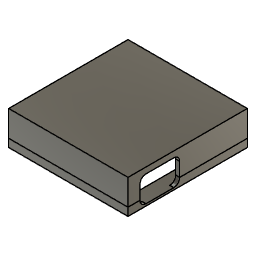
ESP32_Housing (Autodesk Fusion 360 design; units mm, degrees)
Autodesk Fusion 360 part; units mm, degrees
sketch "Sketch1" plane through (0, 0, 0) normal (0, 0, 1) x (1, 0, 0)
  line L0 (0, 0) -> (60, 0)
  line L1 (60, 0) -> (60, 60)
  line L2 (60, 60) -> (0, 60)
  line L3 (0, 60) -> (0, 0)
  line L4 (2, 2) -> (58, 2)
  line L5 (58, 2) -> (58, 58)
  line L6 (58, 58) -> (2, 58)
  line L7 (2, 58) -> (2, 2)
  line L8 (7.5, 7.5) -> (52.5, 7.5)
  line L9 (52.5, 7.5) -> (52.5, 52.5)
  line L10 (52.5, 52.5) -> (7.5, 52.5)
  line L11 (7.5, 52.5) -> (7.5, 7.5)
  dimension "d1" = 60
  dimension "d2" = 60
  dimension "d3" = 56
  dimension "d4" = 56
  dimension "d5" = 2
  dimension "d6" = 2
  dimension "d7" = 45
  dimension "d8" = 45
  dimension "d9" = 7.5
  dimension "d10" = 7.5
  constraint horizontal L0
  constraint vertical L1
  constraint horizontal L2
  constraint vertical L3
  constraint coincident L0.start L3.end
  constraint horizontal L4
  constraint vertical L5
  constraint horizontal L6
  constraint vertical L7
  constraint horizontal L8
  constraint vertical L9
  constraint horizontal L10
  constraint vertical L11
  measures "d1" distance of L0.start L0.end
  measures "d2" distance of L0.start L2.end
  measures "d3" distance of L4.start L4.end
  measures "d4" distance of L4.start L6.end
  measures "d5" distance of L3 L7
  measures "d6" distance of L0 L4
  measures "d7" distance of L8.start L8.end
  measures "d8" distance of L8.start L10.end
  measures "d9" distance of L3 L11
  measures "d10" distance of L0 L8
extrude "Extrude1" add sketch "Sketch1" along normal blind 1 contours L4 L5 L6 L7 makes body 1
extrude "Extrude2" add sketch "Sketch1" along normal blind 4 contours L0 L1 L2 L3 bodies 1
sketch "Sketch2" plane through (0, 0, 4) normal (0, 0, 1) x (-1, 0, 0)
  line L0 (-2, -2) -> (-2, -58)
  line L1 (-2, -58) -> (-58, -58)
  line L2 (-58, -58) -> (-58, -2)
  line L3 (-58, -2) -> (-2, -2)
  line L4 (0, -60) -> (0, 0)
  line L5 (0, 0) -> (-60, 0)
  line L6 (-60, 0) -> (-60, -60)
  line L7 (-60, -60) -> (0, -60)
  line L8 (0, -60) -> (-60, -60)
  line L9 (-60, -60) -> (-60, 0)
  line L10 (-60, 0) -> (0, 0)
  line L11 (0, 0) -> (0, -60)
  line L12 (-30, -60) -> (-30, -50)
  line L13 (-24.25, -60) -> (-35.75, -60)
  line L14 (-35.75, -60) -> (-35.75, -58)
  line L15 (-35.75, -58) -> (-24.25, -58)
  line L16 (-24.25, -58) -> (-24.25, -60)
  line L17 (-60, -30) -> (-53, -30)
  line L18 (-60, -26) -> (-58, -26)
  line L19 (-58, -26) -> (-58, -6)
  line L20 (-58, -6) -> (-60, -6)
  line L21 (-60, -6) -> (-60, -26)
  line L22 (-2, -50) -> (0, -50)
  line L23 (0, -50) -> (0, -15)
  line L24 (0, -15) -> (-2, -15)
  line L25 (-2, -15) -> (-2, -50)
  dimension "d15" = 11.5
  dimension "d16" = 5.75
  dimension "d17" = 20
  dimension "d18" = 4
  dimension "d19" = 2
  dimension "d20" = 35
  dimension "d21" = 10
  constraint horizontal L8
  constraint vertical L9
  constraint horizontal L10
  constraint vertical L11
  constraint coincident L5.end L6.start
  constraint coincident L4.start L7.end
  constraint midpoint L7 L12.start
  constraint perpendicular L1 L12
  constraint horizontal L13
  constraint vertical L14
  constraint horizontal L15
  constraint vertical L16
  constraint coincident L8 L13.start
  constraint midpoint L6 L17.start
  constraint perpendicular L2 L17
  constraint horizontal L18
  constraint vertical L19
  constraint horizontal L20
  constraint vertical L21
  constraint coincident L6 L18.start
  constraint horizontal L22
  constraint vertical L23
  constraint horizontal L24
  constraint vertical L25
  constraint coincident L0 L22.start
  measures "d15" distance of L13.start L13.end
  measures "d16" distance of L12 L16
  measures "d17" distance of L18.start L20.end
  measures "d18" distance of L17 L18
  measures "d19" distance of L22.start L22.end
  measures "d20" distance of L22.start L24.end
  measures "d21" distance of L8 L22.end
extrude "Extrude3" cut sketch "Sketch2" against normal blind 3 contours L0 L4 L11 L22 L23 L24 L25 | L2 L6 L9 L18 L19 L20 L21 | L1 L7 L8 L12 L13 L15 L16 | L1 L7 L8 L12 L13 L14 L15 bodies 1
fillet "Fillet1" radius 3 4 edges at (1, 50, 1) (59, 6, 1) (1, 15, 1) (59, 26, 1) on bodies 1
sketch "Sketch3" plane through (0, 0, 4) normal (0, 0, 1) x (-1, 0, 0)
  line L0 (0, -50) -> (-2, -50)
  line L1 (-2, -50) -> (-2, -58)
  line L2 (-2, -58) -> (-24.25, -58)
  line L3 (-24.25, -58) -> (-24.25, -60)
  line L4 (-24.25, -60) -> (0, -60)
  line L5 (0, -60) -> (0, -50)
  line L6 (0, -60) -> (-60, -60)
  line L7 (-60, -60) -> (-60, 0)
  line L8 (-60, 0) -> (0, 0)
  line L9 (0, 0) -> (0, -60)
  line L10 (-2, -58) -> (-58, -58)
  line L11 (-58, -58) -> (-58, -2)
  line L12 (-58, -2) -> (-2, -2)
  line L13 (-2, -2) -> (-2, -58)
  constraint horizontal L6
  constraint vertical L7
  constraint horizontal L8
  constraint vertical L9
  constraint coincident L4.end L5.start
  constraint horizontal L10
  constraint vertical L11
  constraint horizontal L12
  constraint vertical L13
  constraint coincident L1.end L2.start
extrude "Extrude4" add sketch "Sketch3" along normal blind 12 separate body contours L0 L1 L2 L3 L4 L5 L6 L9 L10 L13 | L0 L3 L6 L7 L8 L9 L10 L11 L12 L13 makes body 2
sketch "Sketch4" plane through (0, 0, 16) normal (0, 0, 1) x (-1, 0, 0)
  line L0 (-58, -2) -> (-2, -2)
  line L1 (-2, -2) -> (-2, -58)
  line L2 (-2, -58) -> (-58, -58)
  line L3 (-58, -58) -> (-58, -2)
  line L4 (0, 0) -> (-60, 0)
  line L5 (-60, 0) -> (-60, -60)
  line L6 (-60, -60) -> (0, -60)
  line L7 (0, -60) -> (0, 0)
  line L8 (0, -60) -> (-60, -60)
  line L9 (-60, -60) -> (-60, 0)
  line L10 (-60, 0) -> (0, 0)
  line L11 (0, 0) -> (0, -60)
  constraint horizontal L8
  constraint vertical L9
  constraint horizontal L10
  constraint vertical L11
  constraint coincident L6.end L7.start
extrude "Extrude5" add sketch "Sketch4" along normal blind 1 contours L0 L1 L2 L3 | L4 L5 L6 L7 L8 L9 L10 L11 bodies 2
extrude "Extrude6" cut sketch "Sketch2" along normal blind 10 contours L0 L4 L11 L22 L23 L24 L25 | L2 L6 L9 L18 L19 L20 L21 bodies 2
fillet "Fillet2" radius 3 4 edges at (59, 6, 14) (1, 15, 14) (59, 26, 14) (1, 50, 14) on bodies 2
sketch "Sketch5" plane through (0, 0, 0) normal (0, 0, 1) x (1, 0, 0)
  line L0 (0, 0) -> (60, 0)
  line L1 (60, 0) -> (60, 60)
  line L2 (60, 60) -> (0, 60)
  line L3 (0, 60) -> (0, 0)
  line L4 (2, 2) -> (4, 2)
  line L5 (4, 2) -> (4, 4)
  line L6 (4, 4) -> (2, 4)
  line L7 (2, 4) -> (2, 2)
  line L8 (58, 2) -> (56, 2)
  line L9 (56, 2) -> (56, 4)
  line L10 (56, 4) -> (58, 4)
  line L11 (58, 4) -> (58, 2)
  line L12 (2, 58) -> (4, 58)
  line L13 (4, 58) -> (4, 56)
  line L14 (4, 56) -> (2, 56)
  line L15 (2, 56) -> (2, 58)
  line L16 (58, 58) -> (56, 58)
  line L17 (56, 58) -> (56, 56)
  line L18 (56, 56) -> (58, 56)
  line L19 (58, 56) -> (58, 58)
  constraint horizontal L0
  constraint vertical L1
  constraint horizontal L2
  constraint vertical L3
  constraint coincident L0.start L3.end
  constraint horizontal L4
  constraint vertical L5
  constraint horizontal L6
  constraint vertical L7
  constraint horizontal L8
  constraint vertical L9
  constraint horizontal L10
  constraint vertical L11
  constraint horizontal L12
  constraint vertical L13
  constraint horizontal L14
  constraint vertical L15
  constraint horizontal L16
  constraint vertical L17
  constraint horizontal L18
  constraint vertical L19
extrude "Extrude7" add sketch "Sketch5" along normal blind 16 contours L4 L5 L6 L7 | L8 L9 L10 L11 | L12 L13 L14 L15 | L16 L17 L18 L19 bodies 2
extrude "Extrude8" cut 4 faces at (2.6667, 3.3333, 0) (57.3333, 2.6667, 0) (56.6667, 57.3333, 0) (2.6667, 57.3333, 0) along direction (0, 0, 1) blind 2 on bodies 2 bodies 2
chamfer "Chamfer1" distance 1.5 angle 45 4 edges at (56, 56, 9) (56, 4, 9) (4, 4, 9) (4, 56, 9) on bodies 2
fillet "Fillet3" radius 0.5 8 edges at (57, 58, 2) (58, 57, 2) (58, 3, 2) (57, 2, 2) (3, 2, 2) (2, 3, 2) (2, 57, 2) (3, 58, 2) on bodies 2
sketch "Sketch6" plane through (0, 0, 4) normal (0, 0, 1) x (-1, 0, 0)
  line L0 (0, -50) -> (-2, -50)
  line L1 (-2, -50) -> (-2, -58)
  line L2 (-2, -58) -> (-24.25, -58)
  line L3 (-24.25, -58) -> (-24.25, -60)
  line L4 (-24.25, -60) -> (0, -60)
  line L5 (0, -60) -> (0, -50)
  line L6 (-2, -58) -> (-58, -58)
  line L7 (-58, -58) -> (-58, -2)
  line L8 (-58, -2) -> (-2, -2)
  line L9 (-2, -2) -> (-2, -58)
  line L10 (-56, -4) -> (-59, -4)
  line L11 (-59, -4) -> (-59, -1)
  line L12 (-59, -1) -> (-56, -1)
  line L13 (-56, -1) -> (-56, -4)
  line L14 (-4, -4) -> (-1, -4)
  line L15 (-1, -4) -> (-1, -1)
  line L16 (-1, -1) -> (-4, -1)
  line L17 (-4, -1) -> (-4, -4)
  line L18 (-1, -59) -> (-4, -59)
  line L19 (-4, -59) -> (-4, -56)
  line L20 (-4, -56) -> (-1, -56)
  line L21 (-1, -56) -> (-1, -59)
  line L22 (-59, -59) -> (-56, -59)
  line L23 (-56, -59) -> (-56, -56)
  line L24 (-56, -56) -> (-59, -56)
  line L25 (-59, -56) -> (-59, -59)
  constraint horizontal L6
  constraint vertical L7
  constraint horizontal L8
  constraint vertical L9
  constraint coincident L1.end L2.start
  constraint horizontal L10
  constraint vertical L11
  constraint horizontal L12
  constraint vertical L13
  constraint horizontal L14
  constraint vertical L15
  constraint horizontal L16
  constraint vertical L17
  constraint horizontal L18
  constraint vertical L19
  constraint horizontal L20
  constraint vertical L21
  constraint horizontal L22
  constraint vertical L23
  constraint horizontal L24
  constraint vertical L25
extrude "Extrude9" cut sketch "Sketch6" against normal blind 3 contours L1 L2 L6 L9 L18 L19 L20 L21 | L8 L9 L14 L15 L16 L17 | L6 L7 L22 L23 L24 L25 | L7 L8 L10 L11 L12 L13 bodies 1
fillet "Fillet4" radius 1 7 edges at (56, 2, 2.5) (2, 4, 2.5) (4, 2, 2.5) (2, 56, 2.5) (4, 58, 2.5) (56, 58, 2.5) (58, 56, 2.5) on bodies 1
extrude "Extrude10" cut 1 faces at (35.75, 59.3333, 3) along direction (1, 0, 0) blind 0.25 on bodies 1 bodies 1
extrude "Extrude11" cut 1 faces at (24.25, 58.6667, 3) along direction (-1, 0, 0) blind 0.25 on bodies 1 bodies 1
fillet "Fillet5" radius 1 1 edges at (58, 4, 2.5) on bodies 1
equation "d16 = ( ( 11.5 ) / 2 ) * 1 mm"
